Autodesk Fusion 360 part; units mm, degrees
(part 5 of 6)
sketch "Skizze9" plane through (0, 0, 0) normal (0, 1, 0) x (1, 0, 0)
  spline S0 degree 5 poles (100, 0) (99.9599, -0.0026) (99.8783, -0.0078) (99.7514, -0.0159) (99.5736, -0.0272) (99.3368, -0.0422) (99.0859, -0.058) (98.8215, -0.0747) (98.5446, -0.0922) (98.2562, -0.1105) (97.9576, -0.1296) (97.6501, -0.1494) (97.3347, -0.1698) (97.0124, -0.1908) (96.6841, -0.2122) (96.3507, -0.2339) (96.013, -0.256) (95.6718, -0.2783) (95.328, -0.3008) (94.9821, -0.3235) (94.6349, -0.3465) (94.2867, -0.3695) (93.9378, -0.3928) (93.5884, -0.4161) (93.2386, -0.4396) (92.8883, -0.4632) (92.5376, -0.4869) (92.1865, -0.5106) (91.8352, -0.5344) (91.4836, -0.5582) (91.1319, -0.5821) (90.7802, -0.606) (90.4285, -0.6299) (90.0769, -0.6539) (89.7253, -0.678) (89.3737, -0.7023) (89.022, -0.7267) (88.6703, -0.7512) (88.3186, -0.7759) (87.9668, -0.8006) (87.6149, -0.8254) (87.263, -0.8502) (86.9111, -0.8749) (86.5592, -0.8995) (86.2073, -0.9241) (85.8554, -0.9488) (85.5035, -0.9735) (85.1516, -0.9983) (84.7997, -1.0232) (84.4478, -1.0482) (84.096, -1.0733) (83.7441, -1.0984) (83.3921, -1.1236) (83.0402, -1.1487) (82.6882, -1.1738) (82.3362, -1.1989) (81.9842, -1.2239) (81.6322, -1.2489) (81.2802, -1.2739) (80.9282, -1.2989) (80.5763, -1.3239) (80.2243, -1.3489) (79.8723, -1.374) (79.5203, -1.3991) (79.1682, -1.4243) (78.8161, -1.4495) (78.464, -1.4747) (78.1119, -1.5) (77.7598, -1.5252) (77.4078, -1.5505) (77.0559, -1.5758) (76.704, -1.601) (76.3522, -1.6263) (76.0003, -1.6515) (75.6485, -1.6767) (75.2966, -1.7019) (74.9448, -1.727) (74.5929, -1.7521) (74.2409, -1.7771) (73.889, -1.802) (73.5371, -1.8269) (73.1851, -1.8516) (72.8332, -1.8763) (72.4813, -1.901) (72.1294, -1.9256) (71.7776, -1.9501) (71.4257, -1.9746) (71.0739, -1.9991) (70.7221, -2.0236) (70.3703, -2.0481) (70.0185, -2.0726) (69.6667, -2.0971) (69.3149, -2.1216) (68.9631, -2.146) (68.6113, -2.1702) (68.2594, -2.1944) (67.9075, -2.2184) (67.5557, -2.2422) (67.2038, -2.266) (66.852, -2.2897) (66.5001, -2.3133) (66.1483, -2.337) (65.7966, -2.3607) (65.4448, -2.3844) (65.0931, -2.4081) (64.7414, -2.4316) (64.3896, -2.455) (64.0378, -2.4783) (63.686, -2.5013) (63.3342, -2.5241) (62.9824, -2.5469) (62.6307, -2.5695) (62.2789, -2.592) (61.9273, -2.6145) (61.5756, -2.637) (61.2239, -2.6595) (60.8722, -2.6819) (60.5205, -2.7044) (60.1687, -2.7268) (59.8169, -2.7491) (59.4651, -2.7713) (59.1133, -2.7933) (58.7615, -2.8151) (58.4097, -2.8366) (58.058, -2.858) (57.7063, -2.8792) (57.3545, -2.9002) (57.0028, -2.9212) (56.651, -2.9422) (56.2992, -2.9632) (55.9474, -2.9841) (55.5955, -3.0049) (55.2436, -3.0257) (54.8918, -3.0462) (54.54, -3.0667) (54.1882, -3.0869) (53.8365, -3.107) (53.4847, -3.1269) (53.133, -3.1467) (52.7812, -3.1665) (52.4295, -3.1862) (52.0777, -3.2058) (51.7259, -3.2253) (51.3741, -3.2447) (51.0223, -3.2639) (50.6705, -3.283) (50.3187, -3.3019) (49.9669, -3.3207) (49.6151, -3.3393) (49.2633, -3.3578) (48.9115, -3.3761) (48.5596, -3.3943) (48.2078, -3.4124) (47.856, -3.4303) (47.5042, -3.4482) (47.1524, -3.4659) (46.8006, -3.4835) (46.4488, -3.5009) (46.097, -3.5182) (45.7451, -3.5353) (45.3932, -3.5522) (45.0412, -3.5689) (44.6892, -3.5855) (44.3371, -3.602) (43.9852, -3.6184) (43.6333, -3.6349) (43.2816, -3.6513) (42.93, -3.6676) (42.5786, -3.6839) (42.2273, -3.6999) (41.876, -3.7156) (41.5249, -3.731) (41.1738, -3.7459) (40.8227, -3.7604) (40.4717, -3.7745) (40.1207, -3.7882) (39.7697, -3.8016) (39.4187, -3.8147) (39.0677, -3.8274) (38.7168, -3.8399) (38.3659, -3.852) (38.0151, -3.8637) (37.6643, -3.875) (37.3136, -3.8858) (36.963, -3.8962) (36.6123, -3.9062) (36.2617, -3.9156) (35.9112, -3.9246) (35.5606, -3.933) (35.2101, -3.941) (34.8596, -3.9485) (34.5091, -3.9554) (34.1587, -3.9619) (33.8083, -3.968) (33.458, -3.9735) (33.1077, -3.9785) (32.7574, -3.9831) (32.4071, -3.9871) (32.0568, -3.9907) (31.7065, -3.9937) (31.3561, -3.9962) (31.0058, -3.9981) (30.6555, -3.9994) (30.3051, -4.0002) (29.9548, -4.0004) (29.6045, -4.0001) (29.2541, -3.9991) (28.9038, -3.9977) (28.5535, -3.9957) (28.2031, -3.9932) (27.8527, -3.9902) (27.5022, -3.9866) (27.1518, -3.9826) (26.8014, -3.9781) (26.4509, -3.9731) (26.1005, -3.9676) (25.7501, -3.9616) (25.3997, -3.9551) (25.0493, -3.9482) (24.6989, -3.9408) (24.3486, -3.9329) (23.9982, -3.9245) (23.648, -3.9156) (23.2977, -3.9062) (22.9475, -3.8963) (22.5973, -3.8858) (22.2471, -3.8748) (21.897, -3.8633) (21.5469, -3.8512) (21.1967, -3.8387) (20.8466, -3.8256) (20.4965, -3.8121) (20.1465, -3.798) (19.7966, -3.7833) (19.4468, -3.7681) (19.0971, -3.7523) (18.7477, -3.7359) (18.3984, -3.7188) (18.0492, -3.7011) (17.7002, -3.6829) (17.3513, -3.6639) (17.0024, -3.6444) (16.6536, -3.6242) (16.305, -3.6033) (15.9565, -3.5816) (15.6083, -3.5591) (15.2603, -3.5358) (14.9127, -3.5116) (14.5653, -3.4864) (14.2182, -3.4604) (13.8713, -3.4334) (13.5246, -3.4054) (13.1782, -3.3764) (12.8319, -3.3464) (12.4859, -3.3154) (12.1402, -3.2833) (11.7948, -3.25) (11.4497, -3.2155) (11.1051, -3.1797) (10.7609, -3.1427) (10.417, -3.1044) (10.0736, -3.0648) (9.7305, -3.0239) (9.388, -2.9816) (9.0459, -2.9379) (8.7045, -2.8927) (8.3637, -2.8461) (8.0238, -2.7979) (7.6848, -2.7482) (7.347, -2.6969) (7.0105, -2.6441) (6.6756, -2.5896) (6.3425, -2.5336) (6.0116, -2.4758) (5.6833, -2.4162) (5.3578, -2.3546) (5.0358, -2.291) (4.7179, -2.2253) (4.4046, -2.1574) (4.097, -2.0874) (3.7958, -2.0156) (3.5021, -1.9419) (3.2169, -1.8665) (2.9409, -1.7893) (2.6751, -1.7101) (2.42, -1.6289) (2.1762, -1.5453) (1.9441, -1.4597) (1.724, -1.3723) (1.516, -1.2839) (1.3201, -1.1946) (1.1361, -1.1042) (0.9639, -1.0119) (0.803, -0.9172) (0.6532, -0.821) (0.5143, -0.7255) (0.3866, -0.6316) (0.2711, -0.5345) (0.1699, -0.4251) (0.0863, -0.3012) (0.0257, -0.1765) (0.0001, -0.0919) (-0.0053, -0.0411) (-0.0028, -0.0128) (0, 0) knots 0 0 0 0 0 0 0.00333333 0.00666667 0.01 0.01333333 0.01666667 0.02 0.02333333 0.02666667 0.03 0.03333333 0.03666667 0.04 0.04333333 0.04666667 0.05 0.05333333 0.05666667 0.06 0.06333333 0.06666667 0.07 0.07333333 0.07666667 0.08 0.08333333 0.08666667 0.09 0.09333333 0.09666667 0.1 0.10333333 0.10666667 0.11 0.11333333 0.11666667 0.12 0.12333333 0.12666667 0.13 0.13333333 0.13666667 0.14 0.14333333 0.14666667 0.15 0.15333333 0.15666667 0.16 0.16333333 0.16666667 0.17 0.17333333 0.17666667 0.18 0.18333333 0.18666667 0.19 0.19333333 0.19666667 0.2 0.20333333 0.20666667 0.21 0.21333333 0.21666667 0.22 0.22333333 0.22666667 0.23 0.23333333 0.23666667 0.24 0.24333333 0.24666667 0.25 0.25333333 0.25666667 0.26 0.26333333 0.26666667 0.27 0.27333333 0.27666667 0.28 0.28333333 0.28666667 0.29 0.29333333 0.29666667 0.3 0.30333333 0.30666667 0.31 0.31333333 0.31666667 0.32 0.32333333 0.32666667 0.33 0.33333333 0.33666667 0.34 0.34333333 0.34666667 0.35 0.35333333 0.35666667 0.36 0.36333333 0.36666667 0.37 0.37333333 0.37666667 0.38 0.38333333 0.38666667 0.39 0.39333333 0.39666667 0.4 0.40333333 0.40666667 0.41 0.41333333 0.41666667 0.42 0.42333333 0.42666667 0.43 0.43333333 0.43666667 0.44 0.44333333 0.44666667 0.45 0.45333333 0.45666667 0.46 0.46333333 0.46666667 0.47 0.47333333 0.47666667 0.48 0.48333333 0.48666667 0.49 0.49333333 0.49666667 0.5 0.50333333 0.50666667 0.51 0.51333333 0.51666667 0.52 0.52333333 0.52666667 0.53 0.53333333 0.53666667 0.54 0.54333333 0.54666667 0.55 0.55333333 0.55666667 0.56 0.56333333 0.56666667 0.57 0.57333333 0.57666667 0.58 0.58333333 0.58666667 0.59 0.59333333 0.59666667 0.6 0.60333333 0.60666667 0.61 0.61333333 0.61666667 0.62 0.62333333 0.62666667 0.63 0.63333333 0.63666667 0.64 0.64333333 0.64666667 0.65 0.65333333 0.65666667 0.66 0.66333333 0.66666667 0.67 0.67333333 0.67666667 0.68 0.68333333 0.68666667 0.69 0.69333333 0.69666667 0.7 0.70333333 0.70666667 0.71 0.71333333 0.71666667 0.72 0.72333333 0.72666667 0.73 0.73333333 0.73666667 0.74 0.74333333 0.74666667 0.75 0.75333333 0.75666667 0.76 0.76333333 0.76666667 0.77 0.77333333 0.77666667 0.78 0.78333333 0.78666667 0.79 0.79333333 0.79666667 0.8 0.80333333 0.80666667 0.81 0.81333333 0.81666667 0.82 0.82333333 0.82666667 0.83 0.83333333 0.83666667 0.84 0.84333333 0.84666667 0.85 0.85333333 0.85666667 0.86 0.86333333 0.86666667 0.87 0.87333333 0.87666667 0.88 0.88333333 0.88666667 0.89 0.89333333 0.89666667 0.9 0.90333333 0.90666667 0.91 0.91333333 0.91666667 0.92 0.92333333 0.92666667 0.93 0.93333333 0.93666667 0.94 0.94333333 0.94666667 0.95 0.95333333 0.95666667 0.96 0.96333333 0.96666667 0.97 0.97333333 0.97666667 0.98 0.98333333 0.98666667 0.99 0.99333333 0.99666667 1 1 1 1 1 1
  spline S1 degree 5 poles (0, 0) (-0.0028, 0.0128) (-0.0053, 0.0411) (0.0001, 0.0919) (0.0257, 0.1765) (0.0863, 0.3012) (0.1699, 0.4251) (0.2711, 0.5345) (0.3866, 0.6316) (0.5143, 0.7255) (0.6532, 0.821) (0.803, 0.9172) (0.9639, 1.0119) (1.1361, 1.1042) (1.3201, 1.1946) (1.516, 1.2839) (1.724, 1.3723) (1.9441, 1.4597) (2.1762, 1.5453) (2.42, 1.6289) (2.6751, 1.7101) (2.9409, 1.7893) (3.2169, 1.8665) (3.5021, 1.9419) (3.7958, 2.0156) (4.097, 2.0874) (4.4046, 2.1574) (4.7179, 2.2253) (5.0358, 2.291) (5.3578, 2.3546) (5.6833, 2.4162) (6.0116, 2.4758) (6.3425, 2.5336) (6.6756, 2.5896) (7.0105, 2.6441) (7.347, 2.6969) (7.6848, 2.7482) (8.0238, 2.7979) (8.3637, 2.8461) (8.7045, 2.8927) (9.0459, 2.9379) (9.388, 2.9816) (9.7305, 3.0239) (10.0736, 3.0648) (10.417, 3.1044) (10.7609, 3.1427) (11.1051, 3.1797) (11.4497, 3.2155) (11.7948, 3.25) (12.1402, 3.2833) (12.4859, 3.3154) (12.8319, 3.3464) (13.1782, 3.3764) (13.5246, 3.4054) (13.8713, 3.4334) (14.2182, 3.4604) (14.5653, 3.4864) (14.9127, 3.5116) (15.2603, 3.5358) (15.6083, 3.5591) (15.9565, 3.5816) (16.305, 3.6033) (16.6536, 3.6242) (17.0024, 3.6444) (17.3513, 3.6639) (17.7002, 3.6829) (18.0492, 3.7011) (18.3984, 3.7188) (18.7477, 3.7359) (19.0971, 3.7523) (19.4468, 3.7681) (19.7966, 3.7833) (20.1465, 3.798) (20.4965, 3.8121) (20.8466, 3.8256) (21.1967, 3.8387) (21.5469, 3.8512) (21.897, 3.8633) (22.2471, 3.8748) (22.5973, 3.8858) (22.9475, 3.8963) (23.2977, 3.9062) (23.648, 3.9156) (23.9982, 3.9245) (24.3486, 3.9329) (24.6989, 3.9408) (25.0493, 3.9482) (25.3997, 3.9551) (25.7501, 3.9616) (26.1005, 3.9676) (26.4509, 3.9731) (26.8014, 3.9781) (27.1518, 3.9826) (27.5022, 3.9866) (27.8527, 3.9902) (28.2031, 3.9932) (28.5535, 3.9957) (28.9038, 3.9977) (29.2541, 3.9991) (29.6045, 4.0001) (29.9548, 4.0004) (30.3051, 4.0002) (30.6555, 3.9994) (31.0058, 3.9981) (31.3561, 3.9962) (31.7065, 3.9937) (32.0568, 3.9907) (32.4071, 3.9871) (32.7574, 3.9831) (33.1077, 3.9785) (33.458, 3.9735) (33.8083, 3.968) (34.1587, 3.9619) (34.5091, 3.9554) (34.8596, 3.9485) (35.2101, 3.941) (35.5606, 3.933) (35.9112, 3.9246) (36.2617, 3.9156) (36.6123, 3.9062) (36.963, 3.8962) (37.3136, 3.8858) (37.6643, 3.875) (38.0151, 3.8637) (38.3659, 3.852) (38.7168, 3.8399) (39.0677, 3.8274) (39.4187, 3.8147) (39.7697, 3.8016) (40.1207, 3.7882) (40.4717, 3.7745) (40.8227, 3.7604) (41.1738, 3.7459) (41.5249, 3.731) (41.876, 3.7156) (42.2273, 3.6999) (42.5786, 3.6839) (42.93, 3.6676) (43.2816, 3.6513) (43.6333, 3.6349) (43.9852, 3.6184) (44.3371, 3.602) (44.6892, 3.5855) (45.0412, 3.5689) (45.3932, 3.5522) (45.7451, 3.5353) (46.097, 3.5182) (46.4488, 3.5009) (46.8006, 3.4835) (47.1524, 3.4659) (47.5042, 3.4482) (47.856, 3.4303) (48.2078, 3.4124) (48.5596, 3.3943) (48.9115, 3.3761) (49.2633, 3.3578) (49.6151, 3.3393) (49.9669, 3.3207) (50.3187, 3.3019) (50.6705, 3.283) (51.0223, 3.2639) (51.3741, 3.2447) (51.7259, 3.2253) (52.0777, 3.2058) (52.4295, 3.1862) (52.7812, 3.1665) (53.133, 3.1467) (53.4847, 3.1269) (53.8365, 3.107) (54.1882, 3.0869) (54.54, 3.0667) (54.8918, 3.0462) (55.2436, 3.0257) (55.5955, 3.0049) (55.9474, 2.9841) (56.2992, 2.9631) (56.651, 2.9422) (57.0028, 2.9212) (57.3546, 2.9002) (57.7063, 2.8792) (58.058, 2.858) (58.4097, 2.8366) (58.7614, 2.8151) (59.1132, 2.7933) (59.465, 2.7713) (59.8168, 2.7491) (60.1686, 2.7268) (60.5205, 2.7044) (60.8723, 2.6819) (61.2242, 2.6595) (61.576, 2.637) (61.9277, 2.6145) (62.2795, 2.592) (62.6312, 2.5695) (62.9828, 2.5469) (63.3345, 2.5242) (63.6861, 2.5013) (64.0378, 2.4783) (64.3896, 2.455) (64.7414, 2.4316) (65.0933, 2.4081) (65.4451, 2.3844) (65.797, 2.3608) (66.1489, 2.3371) (66.5007, 2.3134) (66.8524, 2.2897) (67.2042, 2.266) (67.5559, 2.2422) (67.9076, 2.2184) (68.2594, 2.1944) (68.6111, 2.1702) (68.963, 2.146) (69.3148, 2.1216) (69.6667, 2.0971) (70.0185, 2.0726) (70.3703, 2.0481) (70.7221, 2.0236) (71.074, 1.9991) (71.4258, 1.9746) (71.7776, 1.9501) (72.1294, 1.9256) (72.4813, 1.901) (72.8332, 1.8763) (73.1851, 1.8516) (73.5371, 1.8269) (73.889, 1.802) (74.2409, 1.7771) (74.5929, 1.7521) (74.9448, 1.727) (75.2966, 1.7019) (75.6485, 1.6767) (76.0003, 1.6515) (76.3522, 1.6263) (76.704, 1.601) (77.0559, 1.5758) (77.4078, 1.5505) (77.7598, 1.5252) (78.1119, 1.5) (78.464, 1.4747) (78.8161, 1.4495) (79.1682, 1.4243) (79.5203, 1.3991) (79.8723, 1.374) (80.2243, 1.3489) (80.5763, 1.3239) (80.9282, 1.2989) (81.2802, 1.2739) (81.6322, 1.2489) (81.9842, 1.2239) (82.3362, 1.1989) (82.6882, 1.1738) (83.0402, 1.1487) (83.3921, 1.1236) (83.7441, 1.0984) (84.096, 1.0733) (84.4478, 1.0482) (84.7997, 1.0232) (85.1516, 0.9983) (85.5035, 0.9735) (85.8554, 0.9488) (86.2073, 0.9241) (86.5592, 0.8995) (86.9111, 0.8749) (87.263, 0.8502) (87.6149, 0.8254) (87.9668, 0.8006) (88.3186, 0.7759) (88.6703, 0.7512) (89.022, 0.7267) (89.3737, 0.7023) (89.7253, 0.678) (90.0769, 0.6539) (90.4285, 0.6299) (90.7802, 0.606) (91.1319, 0.5821) (91.4836, 0.5582) (91.8352, 0.5344) (92.1865, 0.5106) (92.5376, 0.4869) (92.8883, 0.4632) (93.2386, 0.4396) (93.5884, 0.4161) (93.9378, 0.3928) (94.2867, 0.3695) (94.6349, 0.3465) (94.9821, 0.3235) (95.328, 0.3008) (95.6718, 0.2783) (96.013, 0.256) (96.3507, 0.2339) (96.6841, 0.2122) (97.0124, 0.1908) (97.3347, 0.1698) (97.6501, 0.1494) (97.9576, 0.1296) (98.2562, 0.1105) (98.5446, 0.0922) (98.8215, 0.0747) (99.0859, 0.058) (99.3368, 0.0422) (99.5736, 0.0272) (99.7514, 0.0159) (99.8783, 0.0078) (99.9599, 0.0026) (100, 0) knots 0 0 0 0 0 0 0.00333333 0.00666667 0.01 0.01333333 0.01666667 0.02 0.02333333 0.02666667 0.03 0.03333333 0.03666667 0.04 0.04333333 0.04666667 0.05 0.05333333 0.05666667 0.06 0.06333333 0.06666667 0.07 0.07333333 0.07666667 0.08 0.08333333 0.08666667 0.09 0.09333333 0.09666667 0.1 0.10333333 0.10666667 0.11 0.11333333 0.11666667 0.12 0.12333333 0.12666667 0.13 0.13333333 0.13666667 0.14 0.14333333 0.14666667 0.15 0.15333333 0.15666667 0.16 0.16333333 0.16666667 0.17 0.17333333 0.17666667 0.18 0.18333333 0.18666667 0.19 0.19333333 0.19666667 0.2 0.20333333 0.20666667 0.21 0.21333333 0.21666667 0.22 0.22333333 0.22666667 0.23 0.23333333 0.23666667 0.24 0.24333333 0.24666667 0.25 0.25333333 0.25666667 0.26 0.26333333 0.26666667 0.27 0.27333333 0.27666667 0.28 0.28333333 0.28666667 0.29 0.29333333 0.29666667 0.3 0.30333333 0.30666667 0.31 0.31333333 0.31666667 0.32 0.32333333 0.32666667 0.33 0.33333333 0.33666667 0.34 0.34333333 0.34666667 0.35 0.35333333 0.35666667 0.36 0.36333333 0.36666667 0.37 0.37333333 0.37666667 0.38 0.38333333 0.38666667 0.39 0.39333333 0.39666667 0.4 0.40333333 0.40666667 0.41 0.41333333 0.41666667 0.42 0.42333333 0.42666667 0.43 0.43333333 0.43666667 0.44 0.44333333 0.44666667 0.45 0.45333333 0.45666667 0.46 0.46333333 0.46666667 0.47 0.47333333 0.47666667 0.48 0.48333333 0.48666667 0.49 0.49333333 0.49666667 0.5 0.50333333 0.50666667 0.51 0.51333333 0.51666667 0.52 0.52333333 0.52666667 0.53 0.53333333 0.53666667 0.54 0.54333333 0.54666667 0.55 0.55333333 0.55666667 0.56 0.56333333 0.56666667 0.57 0.57333333 0.57666667 0.58 0.58333333 0.58666667 0.59 0.59333333 0.59666667 0.6 0.60333333 0.60666667 0.61 0.61333333 0.61666667 0.62 0.62333333 0.62666667 0.63 0.63333333 0.63666667 0.64 0.64333333 0.64666667 0.65 0.65333333 0.65666667 0.66 0.66333333 0.66666667 0.67 0.67333333 0.67666667 0.68 0.68333333 0.68666667 0.69 0.69333333 0.69666667 0.7 0.70333333 0.70666667 0.71 0.71333333 0.71666667 0.72 0.72333333 0.72666667 0.73 0.73333333 0.73666667 0.74 0.74333333 0.74666667 0.75 0.75333333 0.75666667 0.76 0.76333333 0.76666667 0.77 0.77333333 0.77666667 0.78 0.78333333 0.78666667 0.79 0.79333333 0.79666667 0.8 0.80333333 0.80666667 0.81 0.81333333 0.81666667 0.82 0.82333333 0.82666667 0.83 0.83333333 0.83666667 0.84 0.84333333 0.84666667 0.85 0.85333333 0.85666667 0.86 0.86333333 0.86666667 0.87 0.87333333 0.87666667 0.88 0.88333333 0.88666667 0.89 0.89333333 0.89666667 0.9 0.90333333 0.90666667 0.91 0.91333333 0.91666667 0.92 0.92333333 0.92666667 0.93 0.93333333 0.93666667 0.94 0.94333333 0.94666667 0.95 0.95333333 0.95666667 0.96 0.96333333 0.96666667 0.97 0.97333333 0.97666667 0.98 0.98333333 0.98666667 0.99 0.99333333 0.99666667 1 1 1 1 1 1
  point P0 (99.197, -0.051)
  point P1 (97.999, -0.127)
  point P2 (96.426, -0.229)
  point P3 (94.627, -0.347)
  point P4 (92.758, -0.472)
  point P5 (90.868, -0.6)
  point P6 (88.975, -0.73)
  point P7 (87.08, -0.863)
  point P8 (85.184, -0.996)
  point P9 (83.288, -1.131)
  point P10 (81.391, -1.266)
  point P11 (79.494, -1.401)
  point P12 (77.596, -1.537)
  point P13 (75.7, -1.673)
  point P14 (73.804, -1.808)
  point P15 (71.908, -1.941)
  point P16 (70.013, -2.073)
  point P17 (68.118, -2.204)
  point P18 (66.223, -2.332)
  point P19 (64.329, -2.459)
  point P20 (62.435, -2.582)
  point P21 (60.542, -2.703)
  point P22 (58.648, -2.822)
  point P23 (56.755, -2.936)
  point P24 (54.861, -3.048)
  point P25 (52.968, -3.156)
  point P26 (51.075, -3.261)
  point P27 (49.182, -3.362)
  point P28 (47.289, -3.459)
  point P29 (45.396, -3.552)
  point P30 (43.502, -3.641)
  point P31 (41.614, -3.727)
  point P32 (39.73, -3.803)
  point P33 (37.848, -3.869)
  point P34 (35.969, -3.923)
  point P35 (34.092, -3.963)
  point P36 (32.217, -3.989)
  point P37 (30.342, -4)
  point P38 (28.467, -3.995)
  point P39 (26.591, -3.975)
  point P40 (24.715, -3.941)
  point P41 (22.84, -3.893)
  point P42 (20.966, -3.83)
  point P43 (19.094, -3.752)
  point P44 (17.229, -3.657)
  point P45 (15.37, -3.543)
  point P46 (13.523, -3.405)
  point P47 (11.687, -3.239)
  point P48 (9.867, -3.04)
  point P49 (8.069, -2.804)
  point P50 (6.319, -2.529)
  point P51 (4.678, -2.216)
  point P52 (3.256, -1.876)
  point P53 (2.16, -1.538)
  point P54 (1.378, -1.22)
  point P55 (0.829, -0.931)
  point P56 (0.438, -0.668)
  point P57 (0.166, -0.411)
  point P58 (0.018, -0.141)
  point P59 (0.018, 0.141)
  point P60 (0.166, 0.411)
  point P61 (0.438, 0.668)
  point P62 (0.829, 0.931)
  point P63 (1.378, 1.22)
  point P64 (2.16, 1.538)
  point P65 (3.256, 1.876)
  point P66 (4.678, 2.216)
  point P67 (6.319, 2.529)
  point P68 (8.069, 2.804)
  point P69 (9.867, 3.04)
  point P70 (11.687, 3.239)
  point P71 (13.523, 3.405)
  point P72 (15.37, 3.543)
  point P73 (17.229, 3.657)
  point P74 (19.094, 3.752)
  point P75 (20.966, 3.83)
  point P76 (22.84, 3.893)
  point P77 (24.715, 3.941)
  point P78 (26.591, 3.975)
  point P79 (28.467, 3.995)
  point P80 (30.342, 4)
  point P81 (32.217, 3.989)
  point P82 (34.092, 3.963)
  point P83 (35.969, 3.923)
  point P84 (37.848, 3.869)
  point P85 (39.73, 3.803)
  point P86 (41.614, 3.727)
  point P87 (43.502, 3.641)
  point P88 (45.396, 3.552)
  point P89 (47.289, 3.459)
  point P90 (49.182, 3.362)
  point P91 (51.075, 3.261)
  point P92 (52.968, 3.156)
  point P93 (54.861, 3.048)
  point P94 (56.755, 2.936)
  point P95 (58.648, 2.822)
  point P96 (60.542, 2.703)
  point P97 (62.436, 2.582)
  point P98 (64.329, 2.459)
  point P99 (66.224, 2.332)
  point P100 (68.118, 2.204)
  point P101 (70.013, 2.073)
  point P102 (71.908, 1.941)
  point P103 (73.804, 1.808)
  point P104 (75.7, 1.673)
  point P105 (77.596, 1.537)
  point P106 (79.494, 1.401)
  point P107 (81.391, 1.266)
  point P108 (83.288, 1.131)
  point P109 (85.184, 0.996)
  point P110 (87.08, 0.863)
  point P111 (88.975, 0.73)
  point P112 (90.868, 0.6)
  point P113 (92.758, 0.472)
  point P114 (94.627, 0.347)
  point P115 (96.426, 0.229)
  point P116 (97.999, 0.127)
  point P117 (99.197, 0.051)
surface "Schnitt_HLW_1_Spitze" add patch profiles "Skizze9" section 1 separate body makes body 15
scale "Profiltiefe_HLW_1_Spitze" factor 1 about (0, 0, 0) bodies 15
move_body "Station_HLW_1" bodies 15 to x (1, 0, 0) y (0, 1, 0) z (0, 0, 1) at (18, -285, 0)
loft "Loft_HLW_1" add section 1 face at (37.7471, 0, 1.5982) section 2 face at (44.9622, -285, 1.1416) separate body on bodies 14 15 makes body 16
sketch "Skizze10" plane through (0, 0, 0) normal (0, 1, 0) x (1, 0, 0)
  spline S0 degree 5 poles (100, 0) (99.9599, -0.0026) (99.8783, -0.0078) (99.7514, -0.0159) (99.5736, -0.0272) (99.3368, -0.0422) (99.0859, -0.058) (98.8215, -0.0747) (98.5446, -0.0922) (98.2562, -0.1105) (97.9576, -0.1296) (97.6501, -0.1494) (97.3347, -0.1698) (97.0124, -0.1908) (96.6841, -0.2122) (96.3507, -0.2339) (96.013, -0.256) (95.6718, -0.2783) (95.328, -0.3008) (94.9821, -0.3235) (94.6349, -0.3465) (94.2867, -0.3695) (93.9378, -0.3928) (93.5884, -0.4161) (93.2386, -0.4396) (92.8883, -0.4632) (92.5376, -0.4869) (92.1865, -0.5106) (91.8352, -0.5344) (91.4836, -0.5582) (91.1319, -0.5821) (90.7802, -0.606) (90.4285, -0.6299) (90.0769, -0.6539) (89.7253, -0.678) (89.3737, -0.7023) (89.022, -0.7267) (88.6703, -0.7512) (88.3186, -0.7759) (87.9668, -0.8006) (87.6149, -0.8254) (87.263, -0.8502) (86.9111, -0.8749) (86.5592, -0.8995) (86.2073, -0.9241) (85.8554, -0.9488) (85.5035, -0.9735) (85.1516, -0.9983) (84.7997, -1.0232) (84.4478, -1.0482) (84.096, -1.0733) (83.7441, -1.0984) (83.3921, -1.1236) (83.0402, -1.1487) (82.6882, -1.1738) (82.3362, -1.1989) (81.9842, -1.2239) (81.6322, -1.2489) (81.2802, -1.2739) (80.9282, -1.2989) (80.5763, -1.3239) (80.2243, -1.3489) (79.8723, -1.374) (79.5203, -1.3991) (79.1682, -1.4243) (78.8161, -1.4495) (78.464, -1.4747) (78.1119, -1.5) (77.7598, -1.5252) (77.4078, -1.5505) (77.0559, -1.5758) (76.704, -1.601) (76.3522, -1.6263) (76.0003, -1.6515) (75.6485, -1.6767) (75.2966, -1.7019) (74.9448, -1.727) (74.5929, -1.7521) (74.2409, -1.7771) (73.889, -1.802) (73.5371, -1.8269) (73.1851, -1.8516) (72.8332, -1.8763) (72.4813, -1.901) (72.1294, -1.9256) (71.7776, -1.9501) (71.4257, -1.9746) (71.0739, -1.9991) (70.7221, -2.0236) (70.3703, -2.0481) (70.0185, -2.0726) (69.6667, -2.0971) (69.3149, -2.1216) (68.9631, -2.146) (68.6113, -2.1702) (68.2594, -2.1944) (67.9075, -2.2184) (67.5557, -2.2422) (67.2038, -2.266) (66.852, -2.2897) (66.5001, -2.3133) (66.1483, -2.337) (65.7966, -2.3607) (65.4448, -2.3844) (65.0931, -2.4081) (64.7414, -2.4316) (64.3896, -2.455) (64.0378, -2.4783) (63.686, -2.5013) (63.3342, -2.5241) (62.9824, -2.5469) (62.6307, -2.5695) (62.2789, -2.592) (61.9273, -2.6145) (61.5756, -2.637) (61.2239, -2.6595) (60.8722, -2.6819) (60.5205, -2.7044) (60.1687, -2.7268) (59.8169, -2.7491) (59.4651, -2.7713) (59.1133, -2.7933) (58.7615, -2.8151) (58.4097, -2.8366) (58.058, -2.858) (57.7063, -2.8792) (57.3545, -2.9002) (57.0028, -2.9212) (56.651, -2.9422) (56.2992, -2.9632) (55.9474, -2.9841) (55.5955, -3.0049) (55.2436, -3.0257) (54.8918, -3.0462) (54.54, -3.0667) (54.1882, -3.0869) (53.8365, -3.107) (53.4847, -3.1269) (53.133, -3.1467) (52.7812, -3.1665) (52.4295, -3.1862) (52.0777, -3.2058) (51.7259, -3.2253) (51.3741, -3.2447) (51.0223, -3.2639) (50.6705, -3.283) (50.3187, -3.3019) (49.9669, -3.3207) (49.6151, -3.3393) (49.2633, -3.3578) (48.9115, -3.3761) (48.5596, -3.3943) (48.2078, -3.4124) (47.856, -3.4303) (47.5042, -3.4482) (47.1524, -3.4659) (46.8006, -3.4835) (46.4488, -3.5009) (46.097, -3.5182) (45.7451, -3.5353) (45.3932, -3.5522) (45.0412, -3.5689) (44.6892, -3.5855) (44.3371, -3.602) (43.9852, -3.6184) (43.6333, -3.6349) (43.2816, -3.6513) (42.93, -3.6676) (42.5786, -3.6839) (42.2273, -3.6999) (41.876, -3.7156) (41.5249, -3.731) (41.1738, -3.7459) (40.8227, -3.7604) (40.4717, -3.7745) (40.1207, -3.7882) (39.7697, -3.8016) (39.4187, -3.8147) (39.0677, -3.8274) (38.7168, -3.8399) (38.3659, -3.852) (38.0151, -3.8637) (37.6643, -3.875) (37.3136, -3.8858) (36.963, -3.8962) (36.6123, -3.9062) (36.2617, -3.9156) (35.9112, -3.9246) (35.5606, -3.933) (35.2101, -3.941) (34.8596, -3.9485) (34.5091, -3.9554) (34.1587, -3.9619) (33.8083, -3.968) (33.458, -3.9735) (33.1077, -3.9785) (32.7574, -3.9831) (32.4071, -3.9871) (32.0568, -3.9907) (31.7065, -3.9937) (31.3561, -3.9962) (31.0058, -3.9981) (30.6555, -3.9994) (30.3051, -4.0002) (29.9548, -4.0004) (29.6045, -4.0001) (29.2541, -3.9991) (28.9038, -3.9977) (28.5535, -3.9957) (28.2031, -3.9932) (27.8527, -3.9902) (27.5022, -3.9866) (27.1518, -3.9826) (26.8014, -3.9781) (26.4509, -3.9731) (26.1005, -3.9676) (25.7501, -3.9616) (25.3997, -3.9551) (25.0493, -3.9482) (24.6989, -3.9408) (24.3486, -3.9329) (23.9982, -3.9245) (23.648, -3.9156) (23.2977, -3.9062) (22.9475, -3.8963) (22.5973, -3.8858) (22.2471, -3.8748) (21.897, -3.8633) (21.5469, -3.8512) (21.1967, -3.8387) (20.8466, -3.8256) (20.4965, -3.8121) (20.1465, -3.798) (19.7966, -3.7833) (19.4468, -3.7681) (19.0971, -3.7523) (18.7477, -3.7359) (18.3984, -3.7188) (18.0492, -3.7011) (17.7002, -3.6829) (17.3513, -3.6639) (17.0024, -3.6444) (16.6536, -3.6242) (16.305, -3.6033) (15.9565, -3.5816) (15.6083, -3.5591) (15.2603, -3.5358) (14.9127, -3.5116) (14.5653, -3.4864) (14.2182, -3.4604) (13.8713, -3.4334) (13.5246, -3.4054) (13.1782, -3.3764) (12.8319, -3.3464) (12.4859, -3.3154) (12.1402, -3.2833) (11.7948, -3.25) (11.4497, -3.2155) (11.1051, -3.1797) (10.7609, -3.1427) (10.417, -3.1044) (10.0736, -3.0648) (9.7305, -3.0239) (9.388, -2.9816) (9.0459, -2.9379) (8.7045, -2.8927) (8.3637, -2.8461) (8.0238, -2.7979) (7.6848, -2.7482) (7.347, -2.6969) (7.0105, -2.6441) (6.6756, -2.5896) (6.3425, -2.5336) (6.0116, -2.4758) (5.6833, -2.4162) (5.3578, -2.3546) (5.0358, -2.291) (4.7179, -2.2253) (4.4046, -2.1574) (4.097, -2.0874) (3.7958, -2.0156) (3.5021, -1.9419) (3.2169, -1.8665) (2.9409, -1.7893) (2.6751, -1.7101) (2.42, -1.6289) (2.1762, -1.5453) (1.9441, -1.4597) (1.724, -1.3723) (1.516, -1.2839) (1.3201, -1.1946) (1.1361, -1.1042) (0.9639, -1.0119) (0.803, -0.9172) (0.6532, -0.821) (0.5143, -0.7255) (0.3866, -0.6316) (0.2711, -0.5345) (0.1699, -0.4251) (0.0863, -0.3012) (0.0257, -0.1765) (0.0001, -0.0919) (-0.0053, -0.0411) (-0.0028, -0.0128) (0, 0) knots 0 0 0 0 0 0 0.00333333 0.00666667 0.01 0.01333333 0.01666667 0.02 0.02333333 0.02666667 0.03 0.03333333 0.03666667 0.04 0.04333333 0.04666667 0.05 0.05333333 0.05666667 0.06 0.06333333 0.06666667 0.07 0.07333333 0.07666667 0.08 0.08333333 0.08666667 0.09 0.09333333 0.09666667 0.1 0.10333333 0.10666667 0.11 0.11333333 0.11666667 0.12 0.12333333 0.12666667 0.13 0.13333333 0.13666667 0.14 0.14333333 0.14666667 0.15 0.15333333 0.15666667 0.16 0.16333333 0.16666667 0.17 0.17333333 0.17666667 0.18 0.18333333 0.18666667 0.19 0.19333333 0.19666667 0.2 0.20333333 0.20666667 0.21 0.21333333 0.21666667 0.22 0.22333333 0.22666667 0.23 0.23333333 0.23666667 0.24 0.24333333 0.24666667 0.25 0.25333333 0.25666667 0.26 0.26333333 0.26666667 0.27 0.27333333 0.27666667 0.28 0.28333333 0.28666667 0.29 0.29333333 0.29666667 0.3 0.30333333 0.30666667 0.31 0.31333333 0.31666667 0.32 0.32333333 0.32666667 0.33 0.33333333 0.33666667 0.34 0.34333333 0.34666667 0.35 0.35333333 0.35666667 0.36 0.36333333 0.36666667 0.37 0.37333333 0.37666667 0.38 0.38333333 0.38666667 0.39 0.39333333 0.39666667 0.4 0.40333333 0.40666667 0.41 0.41333333 0.41666667 0.42 0.42333333 0.42666667 0.43 0.43333333 0.43666667 0.44 0.44333333 0.44666667 0.45 0.45333333 0.45666667 0.46 0.46333333 0.46666667 0.47 0.47333333 0.47666667 0.48 0.48333333 0.48666667 0.49 0.49333333 0.49666667 0.5 0.50333333 0.50666667 0.51 0.51333333 0.51666667 0.52 0.52333333 0.52666667 0.53 0.53333333 0.53666667 0.54 0.54333333 0.54666667 0.55 0.55333333 0.55666667 0.56 0.56333333 0.56666667 0.57 0.57333333 0.57666667 0.58 0.58333333 0.58666667 0.59 0.59333333 0.59666667 0.6 0.60333333 0.60666667 0.61 0.61333333 0.61666667 0.62 0.62333333 0.62666667 0.63 0.63333333 0.63666667 0.64 0.64333333 0.64666667 0.65 0.65333333 0.65666667 0.66 0.66333333 0.66666667 0.67 0.67333333 0.67666667 0.68 0.68333333 0.68666667 0.69 0.69333333 0.69666667 0.7 0.70333333 0.70666667 0.71 0.71333333 0.71666667 0.72 0.72333333 0.72666667 0.73 0.73333333 0.73666667 0.74 0.74333333 0.74666667 0.75 0.75333333 0.75666667 0.76 0.76333333 0.76666667 0.77 0.77333333 0.77666667 0.78 0.78333333 0.78666667 0.79 0.79333333 0.79666667 0.8 0.80333333 0.80666667 0.81 0.81333333 0.81666667 0.82 0.82333333 0.82666667 0.83 0.83333333 0.83666667 0.84 0.84333333 0.84666667 0.85 0.85333333 0.85666667 0.86 0.86333333 0.86666667 0.87 0.87333333 0.87666667 0.88 0.88333333 0.88666667 0.89 0.89333333 0.89666667 0.9 0.90333333 0.90666667 0.91 0.91333333 0.91666667 0.92 0.92333333 0.92666667 0.93 0.93333333 0.93666667 0.94 0.94333333 0.94666667 0.95 0.95333333 0.95666667 0.96 0.96333333 0.96666667 0.97 0.97333333 0.97666667 0.98 0.98333333 0.98666667 0.99 0.99333333 0.99666667 1 1 1 1 1 1
  spline S1 degree 5 poles (0, 0) (-0.0028, 0.0128) (-0.0053, 0.0411) (0.0001, 0.0919) (0.0257, 0.1765) (0.0863, 0.3012) (0.1699, 0.4251) (0.2711, 0.5345) (0.3866, 0.6316) (0.5143, 0.7255) (0.6532, 0.821) (0.803, 0.9172) (0.9639, 1.0119) (1.1361, 1.1042) (1.3201, 1.1946) (1.516, 1.2839) (1.724, 1.3723) (1.9441, 1.4597) (2.1762, 1.5453) (2.42, 1.6289) (2.6751, 1.7101) (2.9409, 1.7893) (3.2169, 1.8665) (3.5021, 1.9419) (3.7958, 2.0156) (4.097, 2.0874) (4.4046, 2.1574) (4.7179, 2.2253) (5.0358, 2.291) (5.3578, 2.3546) (5.6833, 2.4162) (6.0116, 2.4758) (6.3425, 2.5336) (6.6756, 2.5896) (7.0105, 2.6441) (7.347, 2.6969) (7.6848, 2.7482) (8.0238, 2.7979) (8.3637, 2.8461) (8.7045, 2.8927) (9.0459, 2.9379) (9.388, 2.9816) (9.7305, 3.0239) (10.0736, 3.0648) (10.417, 3.1044) (10.7609, 3.1427) (11.1051, 3.1797) (11.4497, 3.2155) (11.7948, 3.25) (12.1402, 3.2833) (12.4859, 3.3154) (12.8319, 3.3464) (13.1782, 3.3764) (13.5246, 3.4054) (13.8713, 3.4334) (14.2182, 3.4604) (14.5653, 3.4864) (14.9127, 3.5116) (15.2603, 3.5358) (15.6083, 3.5591) (15.9565, 3.5816) (16.305, 3.6033) (16.6536, 3.6242) (17.0024, 3.6444) (17.3513, 3.6639) (17.7002, 3.6829) (18.0492, 3.7011) (18.3984, 3.7188) (18.7477, 3.7359) (19.0971, 3.7523) (19.4468, 3.7681) (19.7966, 3.7833) (20.1465, 3.798) (20.4965, 3.8121) (20.8466, 3.8256) (21.1967, 3.8387) (21.5469, 3.8512) (21.897, 3.8633) (22.2471, 3.8748) (22.5973, 3.8858) (22.9475, 3.8963) (23.2977, 3.9062) (23.648, 3.9156) (23.9982, 3.9245) (24.3486, 3.9329) (24.6989, 3.9408) (25.0493, 3.9482) (25.3997, 3.9551) (25.7501, 3.9616) (26.1005, 3.9676) (26.4509, 3.9731) (26.8014, 3.9781) (27.1518, 3.9826) (27.5022, 3.9866) (27.8527, 3.9902) (28.2031, 3.9932) (28.5535, 3.9957) (28.9038, 3.9977) (29.2541, 3.9991) (29.6045, 4.0001) (29.9548, 4.0004) (30.3051, 4.0002) (30.6555, 3.9994) (31.0058, 3.9981) (31.3561, 3.9962) (31.7065, 3.9937) (32.0568, 3.9907) (32.4071, 3.9871) (32.7574, 3.9831) (33.1077, 3.9785) (33.458, 3.9735) (33.8083, 3.968) (34.1587, 3.9619) (34.5091, 3.9554) (34.8596, 3.9485) (35.2101, 3.941) (35.5606, 3.933) (35.9112, 3.9246) (36.2617, 3.9156) (36.6123, 3.9062) (36.963, 3.8962) (37.3136, 3.8858) (37.6643, 3.875) (38.0151, 3.8637) (38.3659, 3.852) (38.7168, 3.8399) (39.0677, 3.8274) (39.4187, 3.8147) (39.7697, 3.8016) (40.1207, 3.7882) (40.4717, 3.7745) (40.8227, 3.7604) (41.1738, 3.7459) (41.5249, 3.731) (41.876, 3.7156) (42.2273, 3.6999) (42.5786, 3.6839) (42.93, 3.6676) (43.2816, 3.6513) (43.6333, 3.6349) (43.9852, 3.6184) (44.3371, 3.602) (44.6892, 3.5855) (45.0412, 3.5689) (45.3932, 3.5522) (45.7451, 3.5353) (46.097, 3.5182) (46.4488, 3.5009) (46.8006, 3.4835) (47.1524, 3.4659) (47.5042, 3.4482) (47.856, 3.4303) (48.2078, 3.4124) (48.5596, 3.3943) (48.9115, 3.3761) (49.2633, 3.3578) (49.6151, 3.3393) (49.9669, 3.3207) (50.3187, 3.3019) (50.6705, 3.283) (51.0223, 3.2639) (51.3741, 3.2447) (51.7259, 3.2253) (52.0777, 3.2058) (52.4295, 3.1862) (52.7812, 3.1665) (53.133, 3.1467) (53.4847, 3.1269) (53.8365, 3.107) (54.1882, 3.0869) (54.54, 3.0667) (54.8918, 3.0462) (55.2436, 3.0257) (55.5955, 3.0049) (55.9474, 2.9841) (56.2992, 2.9631) (56.651, 2.9422) (57.0028, 2.9212) (57.3546, 2.9002) (57.7063, 2.8792) (58.058, 2.858) (58.4097, 2.8366) (58.7614, 2.8151) (59.1132, 2.7933) (59.465, 2.7713) (59.8168, 2.7491) (60.1686, 2.7268) (60.5205, 2.7044) (60.8723, 2.6819) (61.2242, 2.6595) (61.576, 2.637) (61.9277, 2.6145) (62.2795, 2.592) (62.6312, 2.5695) (62.9828, 2.5469) (63.3345, 2.5242) (63.6861, 2.5013) (64.0378, 2.4783) (64.3896, 2.455) (64.7414, 2.4316) (65.0933, 2.4081) (65.4451, 2.3844) (65.797, 2.3608) (66.1489, 2.3371) (66.5007, 2.3134) (66.8524, 2.2897) (67.2042, 2.266) (67.5559, 2.2422) (67.9076, 2.2184) (68.2594, 2.1944) (68.6111, 2.1702) (68.963, 2.146) (69.3148, 2.1216) (69.6667, 2.0971) (70.0185, 2.0726) (70.3703, 2.0481) (70.7221, 2.0236) (71.074, 1.9991) (71.4258, 1.9746) (71.7776, 1.9501) (72.1294, 1.9256) (72.4813, 1.901) (72.8332, 1.8763) (73.1851, 1.8516) (73.5371, 1.8269) (73.889, 1.802) (74.2409, 1.7771) (74.5929, 1.7521) (74.9448, 1.727) (75.2966, 1.7019) (75.6485, 1.6767) (76.0003, 1.6515) (76.3522, 1.6263) (76.704, 1.601) (77.0559, 1.5758) (77.4078, 1.5505) (77.7598, 1.5252) (78.1119, 1.5) (78.464, 1.4747) (78.8161, 1.4495) (79.1682, 1.4243) (79.5203, 1.3991) (79.8723, 1.374) (80.2243, 1.3489) (80.5763, 1.3239) (80.9282, 1.2989) (81.2802, 1.2739) (81.6322, 1.2489) (81.9842, 1.2239) (82.3362, 1.1989) (82.6882, 1.1738) (83.0402, 1.1487) (83.3921, 1.1236) (83.7441, 1.0984) (84.096, 1.0733) (84.4478, 1.0482) (84.7997, 1.0232) (85.1516, 0.9983) (85.5035, 0.9735) (85.8554, 0.9488) (86.2073, 0.9241) (86.5592, 0.8995) (86.9111, 0.8749) (87.263, 0.8502) (87.6149, 0.8254) (87.9668, 0.8006) (88.3186, 0.7759) (88.6703, 0.7512) (89.022, 0.7267) (89.3737, 0.7023) (89.7253, 0.678) (90.0769, 0.6539) (90.4285, 0.6299) (90.7802, 0.606) (91.1319, 0.5821) (91.4836, 0.5582) (91.8352, 0.5344) (92.1865, 0.5106) (92.5376, 0.4869) (92.8883, 0.4632) (93.2386, 0.4396) (93.5884, 0.4161) (93.9378, 0.3928) (94.2867, 0.3695) (94.6349, 0.3465) (94.9821, 0.3235) (95.328, 0.3008) (95.6718, 0.2783) (96.013, 0.256) (96.3507, 0.2339) (96.6841, 0.2122) (97.0124, 0.1908) (97.3347, 0.1698) (97.6501, 0.1494) (97.9576, 0.1296) (98.2562, 0.1105) (98.5446, 0.0922) (98.8215, 0.0747) (99.0859, 0.058) (99.3368, 0.0422) (99.5736, 0.0272) (99.7514, 0.0159) (99.8783, 0.0078) (99.9599, 0.0026) (100, 0) knots 0 0 0 0 0 0 0.00333333 0.00666667 0.01 0.01333333 0.01666667 0.02 0.02333333 0.02666667 0.03 0.03333333 0.03666667 0.04 0.04333333 0.04666667 0.05 0.05333333 0.05666667 0.06 0.06333333 0.06666667 0.07 0.07333333 0.07666667 0.08 0.08333333 0.08666667 0.09 0.09333333 0.09666667 0.1 0.10333333 0.10666667 0.11 0.11333333 0.11666667 0.12 0.12333333 0.12666667 0.13 0.13333333 0.13666667 0.14 0.14333333 0.14666667 0.15 0.15333333 0.15666667 0.16 0.16333333 0.16666667 0.17 0.17333333 0.17666667 0.18 0.18333333 0.18666667 0.19 0.19333333 0.19666667 0.2 0.20333333 0.20666667 0.21 0.21333333 0.21666667 0.22 0.22333333 0.22666667 0.23 0.23333333 0.23666667 0.24 0.24333333 0.24666667 0.25 0.25333333 0.25666667 0.26 0.26333333 0.26666667 0.27 0.27333333 0.27666667 0.28 0.28333333 0.28666667 0.29 0.29333333 0.29666667 0.3 0.30333333 0.30666667 0.31 0.31333333 0.31666667 0.32 0.32333333 0.32666667 0.33 0.33333333 0.33666667 0.34 0.34333333 0.34666667 0.35 0.35333333 0.35666667 0.36 0.36333333 0.36666667 0.37 0.37333333 0.37666667 0.38 0.38333333 0.38666667 0.39 0.39333333 0.39666667 0.4 0.40333333 0.40666667 0.41 0.41333333 0.41666667 0.42 0.42333333 0.42666667 0.43 0.43333333 0.43666667 0.44 0.44333333 0.44666667 0.45 0.45333333 0.45666667 0.46 0.46333333 0.46666667 0.47 0.47333333 0.47666667 0.48 0.48333333 0.48666667 0.49 0.49333333 0.49666667 0.5 0.50333333 0.50666667 0.51 0.51333333 0.51666667 0.52 0.52333333 0.52666667 0.53 0.53333333 0.53666667 0.54 0.54333333 0.54666667 0.55 0.55333333 0.55666667 0.56 0.56333333 0.56666667 0.57 0.57333333 0.57666667 0.58 0.58333333 0.58666667 0.59 0.59333333 0.59666667 0.6 0.60333333 0.60666667 0.61 0.61333333 0.61666667 0.62 0.62333333 0.62666667 0.63 0.63333333 0.63666667 0.64 0.64333333 0.64666667 0.65 0.65333333 0.65666667 0.66 0.66333333 0.66666667 0.67 0.67333333 0.67666667 0.68 0.68333333 0.68666667 0.69 0.69333333 0.69666667 0.7 0.70333333 0.70666667 0.71 0.71333333 0.71666667 0.72 0.72333333 0.72666667 0.73 0.73333333 0.73666667 0.74 0.74333333 0.74666667 0.75 0.75333333 0.75666667 0.76 0.76333333 0.76666667 0.77 0.77333333 0.77666667 0.78 0.78333333 0.78666667 0.79 0.79333333 0.79666667 0.8 0.80333333 0.80666667 0.81 0.81333333 0.81666667 0.82 0.82333333 0.82666667 0.83 0.83333333 0.83666667 0.84 0.84333333 0.84666667 0.85 0.85333333 0.85666667 0.86 0.86333333 0.86666667 0.87 0.87333333 0.87666667 0.88 0.88333333 0.88666667 0.89 0.89333333 0.89666667 0.9 0.90333333 0.90666667 0.91 0.91333333 0.91666667 0.92 0.92333333 0.92666667 0.93 0.93333333 0.93666667 0.94 0.94333333 0.94666667 0.95 0.95333333 0.95666667 0.96 0.96333333 0.96666667 0.97 0.97333333 0.97666667 0.98 0.98333333 0.98666667 0.99 0.99333333 0.99666667 1 1 1 1 1 1
  point P0 (99.197, -0.051)
  point P1 (97.999, -0.127)
  point P2 (96.426, -0.229)
  point P3 (94.627, -0.347)
  point P4 (92.758, -0.472)
  point P5 (90.868, -0.6)
  point P6 (88.975, -0.73)
  point P7 (87.08, -0.863)
  point P8 (85.184, -0.996)
  point P9 (83.288, -1.131)
  point P10 (81.391, -1.266)
  point P11 (79.494, -1.401)
  point P12 (77.596, -1.537)
  point P13 (75.7, -1.673)
  point P14 (73.804, -1.808)
  point P15 (71.908, -1.941)
  point P16 (70.013, -2.073)
  point P17 (68.118, -2.204)
  point P18 (66.223, -2.332)
  point P19 (64.329, -2.459)
  point P20 (62.435, -2.582)
  point P21 (60.542, -2.703)
  point P22 (58.648, -2.822)
  point P23 (56.755, -2.936)
  point P24 (54.861, -3.048)
  point P25 (52.968, -3.156)
  point P26 (51.075, -3.261)
  point P27 (49.182, -3.362)
  point P28 (47.289, -3.459)
  point P29 (45.396, -3.552)
  point P30 (43.502, -3.641)
  point P31 (41.614, -3.727)
  point P32 (39.73, -3.803)
  point P33 (37.848, -3.869)
  point P34 (35.969, -3.923)
  point P35 (34.092, -3.963)
  point P36 (32.217, -3.989)
  point P37 (30.342, -4)
  point P38 (28.467, -3.995)
  point P39 (26.591, -3.975)
  point P40 (24.715, -3.941)
  point P41 (22.84, -3.893)
  point P42 (20.966, -3.83)
  point P43 (19.094, -3.752)
  point P44 (17.229, -3.657)
  point P45 (15.37, -3.543)
  point P46 (13.523, -3.405)
  point P47 (11.687, -3.239)
  point P48 (9.867, -3.04)
  point P49 (8.069, -2.804)
  point P50 (6.319, -2.529)
  point P51 (4.678, -2.216)
  point P52 (3.256, -1.876)
  point P53 (2.16, -1.538)
  point P54 (1.378, -1.22)
  point P55 (0.829, -0.931)
  point P56 (0.438, -0.668)
  point P57 (0.166, -0.411)
  point P58 (0.018, -0.141)
  point P59 (0.018, 0.141)
  point P60 (0.166, 0.411)
  point P61 (0.438, 0.668)
  point P62 (0.829, 0.931)
  point P63 (1.378, 1.22)
  point P64 (2.16, 1.538)
  point P65 (3.256, 1.876)
  point P66 (4.678, 2.216)
  point P67 (6.319, 2.529)
  point P68 (8.069, 2.804)
  point P69 (9.867, 3.04)
  point P70 (11.687, 3.239)
  point P71 (13.523, 3.405)
  point P72 (15.37, 3.543)
  point P73 (17.229, 3.657)
  point P74 (19.094, 3.752)
  point P75 (20.966, 3.83)
  point P76 (22.84, 3.893)
  point P77 (24.715, 3.941)
  point P78 (26.591, 3.975)
  point P79 (28.467, 3.995)
  point P80 (30.342, 4)
  point P81 (32.217, 3.989)
  point P82 (34.092, 3.963)
  point P83 (35.969, 3.923)
  point P84 (37.848, 3.869)
  point P85 (39.73, 3.803)
  point P86 (41.614, 3.727)
  point P87 (43.502, 3.641)
  point P88 (45.396, 3.552)
  point P89 (47.289, 3.459)
  point P90 (49.182, 3.362)
  point P91 (51.075, 3.261)
  point P92 (52.968, 3.156)
  point P93 (54.861, 3.048)
  point P94 (56.755, 2.936)
  point P95 (58.648, 2.822)
  point P96 (60.542, 2.703)
  point P97 (62.436, 2.582)
  point P98 (64.329, 2.459)
  point P99 (66.224, 2.332)
  point P100 (68.118, 2.204)
  point P101 (70.013, 2.073)
  point P102 (71.908, 1.941)
  point P103 (73.804, 1.808)
  point P104 (75.7, 1.673)
  point P105 (77.596, 1.537)
  point P106 (79.494, 1.401)
  point P107 (81.391, 1.266)
  point P108 (83.288, 1.131)
  point P109 (85.184, 0.996)
  point P110 (87.08, 0.863)
  point P111 (88.975, 0.73)
  point P112 (90.868, 0.6)
  point P113 (92.758, 0.472)
  point P114 (94.627, 0.347)
  point P115 (96.426, 0.229)
  point P116 (97.999, 0.127)
  point P117 (99.197, 0.051)
surface "Schnitt_HLW_2_Spitze" add patch profiles "Skizze10" section 1 separate body makes body 17
scale "Profiltiefe_HLW_2_Spitze" factor 1 about (0, 0, 0) bodies 17
move_body "Station_HLW_2" bodies 17 to x (1, 0, 0) y (0, 1, 0) z (0, 0, 1) at (18, 285, 0)
loft "Loft_HLW_2" add section 1 face at (37.7471, 0, 1.5982) section 2 face at (44.9622, 285, 1.1416) separate body on bodies 14 17 makes body 18
combine "Join_HLW" operation add target body 16 tool bodies 18
move_body "Einstellwinkel_HLW" bodies 16 to x (0.999848, 0, 0.017452) y (0, 1, 0) z (-0.017452, 0, 0.999848) at (0, 0, 0)
move_body "Position_HLW" bodies 16 to x (1, 0, 0) y (0, 1, 0) z (0, 0, 1) at (720, 0, 0)
delete_body "Körper entfernen8" bodies 14
delete_body "Körper entfernen9" bodies 15
delete_body "Körper entfernen10" bodies 17